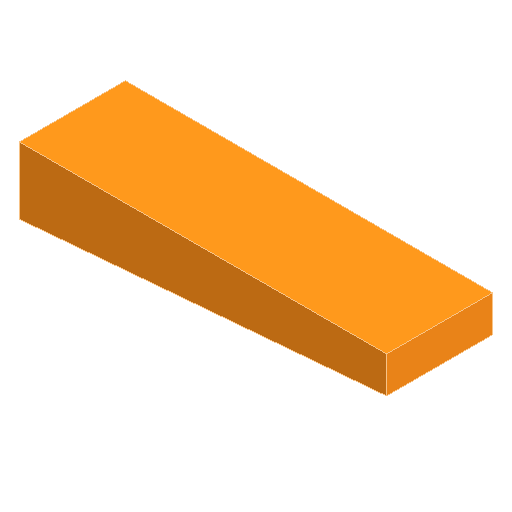
# Autodesk Inventor part: PRT - 9033 - CAMTARKEY - V04
Saved by Autodesk Inventor 2025.5 (Build 295498000, 498)
## iProperties
Created: 2026-11-06
Part Number: PRT - 9033 - CAMTARKEY - V04
Material: Generisch
Description: Wedge key: pushed in from the side between the camera module and the USB-C shell, clamps the module into its seat. Print on its side.
Document SubType Name: Modeling
Designer: benir
Density: 1 g/cm^3
Appearance: Orange
Author: benir
Autodesk Inventor part; units mm, degrees
ref_plane "YZ Plane" through (0, 0, 0) normal (1, 0, 0) x (0, 1, 0)
ref_plane "XZ Plane" through (0, 0, 0) normal (0, 1, 0) x (-1, 0, 0)
ref_plane "z=key_z0" through (0, 0, -2.75) normal (0, 0, 1) x (1, 0, 0)
sketch "key sketch" plane through (0, 0, -2.75) normal (0, 0, 1) x (1, 0, 0)
  line L0 (-15.2, -9.6513) -> (9.75, -7.573)
  line L1 (9.75, -7.573) -> (9.75, -5.1)
  line L2 (9.75, -5.1) -> (-15.2, -5.1)
  line L3 (-15.2, -5.1) -> (-15.2, -9.6513)
  point P0 (0, 0)
  dimension "d1" = 9.6513
  dimension "d2" = 15.2
  dimension "d3" = 7.573
  dimension "d4" = 9.75
  dimension "d5" = 5.1
  dimension "d6" = 9.75
  dimension "d7" = 5.1
  dimension "d8" = 15.2
  constraints: 8 end point
  measures "d1" vertical distance of point (0, 0) L0.start
  measures "d2" horizontal distance of point (0, 0) L0.start
  measures "d3" vertical distance of point (0, 0) L0.end
  measures "d4" horizontal distance of point (0, 0) L0.end
  measures "d5" vertical distance of point (0, 0) L1.end
  measures "d6" horizontal distance of point (0, 0) L1.end
  measures "d7" vertical distance of point (0, 0) L2.end
  measures "d8" horizontal distance of point (0, 0) L2.end
extrude "wedge key" add sketch "key sketch" along normal blind 7.2
equation "\"d1\" = -key_back_head"
equation "\"d2\" = key_x0"
equation "\"d3\" = -key_back_tip"
equation "\"d4\" = key_x1"
equation "\"d5\" = -key_front_y"
equation "\"d6\" = key_x1"
equation "\"d7\" = -key_front_y"
equation "\"d8\" = key_x0"
equation "\"d9\" = key_h"
equation "\"sense_bx1\" = 5.7"
equation "\"cam_bx\" = 8.75"
equation "\"sense_z1\" = sense_bx1 - cam_bx"
equation "\"key_clr\" = 0.15"
equation "\"d0\" = key_z0"
equation "\"body_left\" = 16.7"
equation "\"key_sink\" = 1.5"
equation "\"key_x0\" = body_left - key_sink"
equation "\"usb_front_by\" = 4.21"
equation "\"sensor_y\" = -4.5"
equation "\"sensor_by\" = 8.6"
equation "\"ofs_y\" = sensor_y - sensor_by"
equation "\"usb_front_y\" = usb_front_by + ofs_y"
equation "\"key_gap\" = 0.05"
equation "\"key_y0\" = usb_front_y + key_gap"
equation "\"cam_bz\" = -6.75"
equation "\"usb_bz1\" = -1.65"
equation "\"usb_x0\" = cam_bz - usb_bz1"
equation "\"key_slope\" = 0.0833"
equation "\"main_bz0\" = -15"
equation "\"main_x1\" = cam_bz - main_bz0"
equation "\"clr_board\" = 0.5"
equation "\"pocket_x1\" = main_x1 + clr_board"
equation "\"key_blind\" = 2"
equation "\"slot_x1\" = pocket_x1 + key_blind"
equation "\"mod_back_by\" = 7.95"
equation "\"mod_back_y\" = mod_back_by + ofs_y"
equation "\"key_press\" = 0.05"
equation "\"key_front_y\" = mod_back_y + key_press"
equation "\"key_h\" = 7.2"
equation "\"key_z0\" = -2.75"
equation "\"key_back_head\" = -9.65133"
equation "\"key_back_tip\" = -7.572995"
equation "\"key_x1\" = 9.75"
body "Solid1"
